610000_P01_AIR_CAD (Autodesk Fusion 360 design; units mm, degrees)
description: AIR | Thông gió | HS | P01
part number: 2026-11-01-02-30-39-384
description: AIR - AIR COLUMN | Cột gió (cụm) | HS | P01
part number: 610101
description: AIR - COLUMN FOOT PLATE | Cột gió - tấm chân | MP | P01
part number: 611106
description: AIR - COLUMN FACE - FRONT | Cột gió - mặt trước (ACP + nỉ) | MP | P01
part number: 611101
description: AIR - COLUMN FACE - LEFT | Cột gió - mặt trái (ACP + nỉ) | MP | P01
part number: 611102
description: AIR - COLUMN PLENUM SIDE PLATE - LOW | Cột gió - tấm hông buồng dưới | MP | P01
part number: 611107
description: AIR - COLUMN PLENUM SIDE PLATE - HIGH | Cột gió - tấm hông buồng trên | MP | P01
part number: 611108
description: AIR - COLUMN FILL - FRONT | Cột gió - bông - tấm trước | MP | P01
part number: 611104
description: AIR - COLUMN FILL - LEFT | Cột gió - bông - tấm trái | MP | P01
part number: 611110
description: AIR - KICK GRILLE - FRONT | Lưới gió chân cột - tấm trước | MP | P01
part number: 611105
description: AIR - KICK GRILLE - LEFT | Lưới gió chân cột - tấm trái | MP | P01
part number: 611111
description: AIR - SENSOR HUB ZONE - HOLD | Vùng bộ cảm biến (chờ) | reserved air space | P01
part number: 618101
description: AIR - COLUMN CORNER ANGLE - FRONT | Cột gió - thanh góc nhôm phía trước | MP | P01
part number: 611103
description: AIR - COLUMN CORNER ANGLE - BACK | Cột gió - thanh góc nhôm phía sau | MP | P01
part number: 611109
description: AIR - SPLITTER CARTRIDGE - COMMON | Ống tiêu âm (dùng chung cấp/thải) | HS | P01
part number: 610301
description: AIR - CARTRIDGE CASING | Vỏ ống tiêu âm nhôm 2 mm | MP | P01
part number: 611301
description: AIR - CARTRIDGE FILL - LAYER 50 | Bông tiêu âm - lớp 50 mm | MP | P01
part number: 611302
description: AIR - SOFFIT | Hộp gió trần trên cửa (cụm) | HS | P01
part number: 610201
description: AIR - SOFFIT UNDERSIDE - LEFT HINGED | Hộp gió - mặt dưới trái (bản lề, màu tối) | MP | P01
part number: 611201
description: AIR - SOFFIT UNDERSIDE - RIGHT HINGED | Hộp gió - mặt dưới phải (bản lề, màu tối) | MP | P01
part number: 611207
description: AIR - SOFFIT UNDERSIDE - FIXED OVER THE COLUMN | Hộp gió - mặt dưới cố định trên cột | MP | P01
part number: 611208
description: AIR - SOFFIT FACE - FRONT | Hộp gió - mặt trước | MP | P01
part number: 611202
description: AIR - SOFFIT TOP RAIL - DOOR SIDE | Hộp gió - thanh treo phía cửa | MP | P01
part number: 611205
description: AIR - SOFFIT TOP RAIL - ROOM SIDE | Hộp gió - thanh treo phía trong | MP | P01
part number: 611209
description: AIR - SOFFIT DOOR-SIDE PLATE | Hộp gió - tấm phía cửa | MP | P01
part number: 611210
description: AIR - SOFFIT END PLATE - LEFT | Hộp gió - tấm đầu trái | MP | P01
part number: 611206
description: AIR - SOFFIT FILL | Hộp gió - bông | MP | P01
part number: 611203
description: AIR - SOFFIT FILL - FRONT | Hộp gió - bông - tấm trước | MP | P01
part number: 611211
description: AIR - EXHAUST GRILLE | Lưới gió thải | MP | P01
part number: 611204
description: HARDWARE - SOCKET HEAD BOLT - M6 X 16 - ISO 4762 8.8 ZINC | Bulong lục giác chìm M6 × 16 | PI | P01 | the soffit's hanger stud (D-90)
part number: 838001
description: AIR - SOFFIT UNDERSIDE HINGE - HOLD | Bản lề mặt dưới hộp gió (chờ) | HOLD | P01
part number: 618105
description: AIR - SOFFIT UNDERSIDE LATCH - HOLD | Chốt bấm mặt dưới hộp gió (chờ) | HOLD | P01
part number: 618106
description: HARDWARE - SOCKET HEAD BOLT - M6 X 25 - ISO 4762 8.8 ZINC | Bulong lục giác chìm M6 × 25 (chốt mối nối khép) | PI | P01 | captive retainer HOLD (joints register)
part number: 838002
description: AIR - EXHAUST FAN BOX | Hộp quạt thải (cụm) | HS | P01
part number: 610402
description: AIR - FAN BOX CASING - EXHAUST | Vỏ hộp quạt thải nhôm 3 mm | MP | P01
part number: 611401
description: AIR - FAN BOX BULKHEAD - EXHAUST | Hộp quạt thải - vách ngăn nhôm 2 mm | MP | P01
part number: 611403
description: AIR - FAN BOX LINING - EXHAUST SIDE | Hộp quạt thải - lớp lót bên | MP | P01
part number: 611405
description: AIR - FAN BOX LINING - EXHAUST FAR END | Hộp quạt thải - lớp lót đầu xa | MP | P01
part number: 611406
description: AIR - FAN - NOCTUA NF-A14 INDUSTRIALPPC-3000 PWM | Quạt 12 V 140 mm | PI | P01
part number: 618401
description: AIR - SUPPLY FAN BOX | Hộp quạt cấp (cụm) | HS | P01
part number: 610401
description: AIR - FAN BOX CASING - SUPPLY | Vỏ hộp quạt cấp nhôm 3 mm | MP | P01
part number: 611402
description: AIR - FAN BOX BULKHEAD - SUPPLY | Hộp quạt cấp - vách ngăn | MP | P01
part number: 611404
description: AIR - FAN BOX LINING - SUPPLY END | Hộp quạt cấp - lớp lót đầu | MP | P01
part number: 611407
description: AIR - FAN BOX LIP ANGLE - SUPPLY | Hộp quạt cấp - thanh góc mép nhôm 3 mm | MP | P01
part number: 611408
description: AIR - FAN BOX PAD - SUPPLY - RUBBER 40 X 15 X 5 - HOLD | Hộp quạt cấp - đệm cao su 40 x 15 x 5 (chờ) | PI | P01
part number: 618402
description: AIR - RISER BUFFER - RUBBER - M6 - HOLD | Ống hút gió đứng - đệm cao su ren M6 (chờ) | PI | P01
part number: 618501
description: AIR - SUPPLY TRANSITION - HOLD | Ống chuyển cấp (chờ) | HOLD | P01
part number: 618102
description: AIR - INTAKE RISER | Ống hút gió đứng | MP | P01
part number: 611501
description: AIR - RISER TRANSITION - HOLD | Ống chuyển hút (chờ) | HOLD | P01
part number: 618103
description: AIR - ROOF SLEEVE | Ống thải qua mái | MP | P01
part number: 611601
description: AIR - ROOF GRILLE | Lưới thải mái | MP | P01
part number: 611602
Autodesk Fusion 360 part; units mm, degrees
(part 1 of 6)
ref_plane "WorkPlane1" through (0, 0, 0) normal (0, 0, 1) x (1, 0, 0) in component "611106 AIR - COLUMN FOOT PLATE"
sketch "OUTLINE - COLUMN FOOT PLATE" plane through (0, 0, 0) normal (0, 0, 1) x (1, 0, 0) in component "611106 AIR - COLUMN FOOT PLATE"
  line L0 (949, -641.14) -> (1161, -641.14)
  line L1 (1161, -641.14) -> (1161, -285)
  line L2 (1161, -285) -> (949, -285)
  line L3 (949, -285) -> (949, -641.14)
  dimension "d9773" = 212
  dimension "d9774" = 356.14
  dimension "d9775" = 949
  dimension "d9776" = 641.14
  constraint horizontal L0
  constraint vertical L1
  constraint horizontal L2
  constraint vertical L3
  measures "d9773" horizontal distance of L0.start L0.end
  measures "d9774" vertical distance of L0.start L2.end
  measures "d9775" horizontal distance of origin L0.start
  measures "d9776" vertical distance of origin L0.start
extrude "EXTRUDE - COLUMN FOOT PLATE" add sketch "OUTLINE - COLUMN FOOT PLATE" along normal blind 2 makes body 1 in component "611106 AIR - COLUMN FOOT PLATE"
ref_plane "WorkPlane1" through (0, 0, 112) normal (0, 0, 1) x (1, 0, 0) in component "611101 AIR - COLUMN FACE - FRONT"
sketch "OUTLINE - COLUMN FACE FRONT" plane through (0, 0, 112) normal (0, 0, 1) x (1, 0, 0) in component "611101 AIR - COLUMN FACE - FRONT"
  line L0 (949, -297) -> (1161, -297)
  line L1 (1161, -297) -> (1161, -285)
  line L2 (1161, -285) -> (949, -285)
  line L3 (949, -285) -> (949, -297)
  dimension "d9781" = 212
  dimension "d9782" = 12
  dimension "d9783" = 949
  dimension "d9784" = 297
  constraint horizontal L0
  constraint vertical L1
  constraint horizontal L2
  constraint vertical L3
  measures "d9781" horizontal distance of L0.start L0.end
  measures "d9782" vertical distance of L0.start L2.end
  measures "d9783" horizontal distance of origin L0.start
  measures "d9784" vertical distance of origin L0.start
extrude "EXTRUDE - COLUMN FACE FRONT" add sketch "OUTLINE - COLUMN FACE FRONT" along normal blind 2008 separate body makes body 2 in component "611101 AIR - COLUMN FACE - FRONT"
ref_plane "WorkPlane2" through (0, 0, 1110) normal (0, 0, 1) x (1, 0, 0) in component "611101 AIR - COLUMN FACE - FRONT"
sketch "OUTLINE - COLUMN FACE FRONT OPENING 1" plane through (0, 0, 1110) normal (0, 0, 1) x (1, 0, 0) in component "611101 AIR - COLUMN FACE - FRONT"
  line L0 (971, -337) -> (1151, -337)
  line L1 (1151, -337) -> (1151, -285)
  line L2 (1151, -285) -> (971, -285)
  line L3 (971, -285) -> (971, -337)
  dimension "d9789" = 180
  dimension "d9790" = 52
  dimension "d9791" = 971
  dimension "d9792" = 337
  constraint horizontal L0
  constraint vertical L1
  constraint horizontal L2
  constraint vertical L3
  measures "d9789" horizontal distance of L0.start L0.end
  measures "d9790" vertical distance of L0.start L2.end
  measures "d9791" horizontal distance of origin L0.start
  measures "d9792" vertical distance of origin L0.start
extrude "CUT - COLUMN FACE FRONT OPENING 1" cut sketch "OUTLINE - COLUMN FACE FRONT OPENING 1" along normal blind 180 bodies 2 in component "611101 AIR - COLUMN FACE - FRONT"
ref_plane "WorkPlane1" through (0, 0, 112) normal (0, 0, 1) x (1, 0, 0) in component "611102 AIR - COLUMN FACE - LEFT"
sketch "OUTLINE - COLUMN FACE LEFT" plane through (0, 0, 112) normal (0, 0, 1) x (1, 0, 0) in component "611102 AIR - COLUMN FACE - LEFT"
  line L0 (949, -641.14) -> (961, -641.14)
  line L1 (961, -641.14) -> (961, -297)
  line L2 (961, -297) -> (949, -297)
  line L3 (949, -297) -> (949, -641.14)
  dimension "d9797" = 12
  dimension "d9798" = 344.14
  dimension "d9799" = 949
  dimension "d9800" = 641.14
  constraint horizontal L0
  constraint vertical L1
  constraint horizontal L2
  constraint vertical L3
  measures "d9797" horizontal distance of L0.start L0.end
  measures "d9798" vertical distance of L0.start L2.end
  measures "d9799" horizontal distance of origin L0.start
  measures "d9800" vertical distance of origin L0.start
extrude "EXTRUDE - COLUMN FACE LEFT" add sketch "OUTLINE - COLUMN FACE LEFT" along normal blind 2008 separate body makes body 3 in component "611102 AIR - COLUMN FACE - LEFT"
ref_plane "WorkPlane1" through (0, 0, 2) normal (0, 0, 1) x (1, 0, 0) in component "611107 AIR - COLUMN PLENUM SIDE PLATE - LOW"
sketch "OUTLINE - COLUMN PLENUM PLATE LOW" plane through (0, 0, 2) normal (0, 0, 1) x (1, 0, 0) in component "611107 AIR - COLUMN PLENUM SIDE PLATE - LOW"
  line L0 (1160, -641.14) -> (1161, -641.14)
  line L1 (1161, -641.14) -> (1161, -317)
  line L2 (1161, -317) -> (1160, -317)
  line L3 (1160, -317) -> (1160, -641.14)
  dimension "d9805" = 1
  dimension "d9806" = 324.14
  dimension "d9807" = 1160
  dimension "d9808" = 641.14
  constraint horizontal L0
  constraint vertical L1
  constraint horizontal L2
  constraint vertical L3
  measures "d9805" horizontal distance of L0.start L0.end
  measures "d9806" vertical distance of L0.start L2.end
  measures "d9807" horizontal distance of origin L0.start
  measures "d9808" vertical distance of origin L0.start
extrude "EXTRUDE - COLUMN PLENUM PLATE LOW" add sketch "OUTLINE - COLUMN PLENUM PLATE LOW" along normal blind 138 separate body makes body 4 in component "611107 AIR - COLUMN PLENUM SIDE PLATE - LOW"
ref_plane "WorkPlane1" through (0, 0, 1890) normal (0, 0, 1) x (1, 0, 0) in component "611108 AIR - COLUMN PLENUM SIDE PLATE - HIGH"
sketch "OUTLINE - COLUMN PLENUM PLATE HIGH" plane through (0, 0, 1890) normal (0, 0, 1) x (1, 0, 0) in component "611108 AIR - COLUMN PLENUM SIDE PLATE - HIGH"
  line L0 (1160, -641.14) -> (1161, -641.14)
  line L1 (1161, -641.14) -> (1161, -317)
  line L2 (1161, -317) -> (1160, -317)
  line L3 (1160, -317) -> (1160, -641.14)
  dimension "d9813" = 1
  dimension "d9814" = 324.14
  dimension "d9815" = 1160
  dimension "d9816" = 641.14
  constraint horizontal L0
  constraint vertical L1
  constraint horizontal L2
  constraint vertical L3
  measures "d9813" horizontal distance of L0.start L0.end
  measures "d9814" vertical distance of L0.start L2.end
  measures "d9815" horizontal distance of origin L0.start
  measures "d9816" vertical distance of origin L0.start
extrude "EXTRUDE - COLUMN PLENUM PLATE HIGH" add sketch "OUTLINE - COLUMN PLENUM PLATE HIGH" along normal blind 230 separate body makes body 5 in component "611108 AIR - COLUMN PLENUM SIDE PLATE - HIGH"
ref_plane "WorkPlane1" through (0, 0, 140) normal (0, 0, 1) x (1, 0, 0) in component "611104 AIR - COLUMN FILL - FRONT"
sketch "OUTLINE - COLUMN FILL FRONT" plane through (0, 0, 140) normal (0, 0, 1) x (1, 0, 0) in component "611104 AIR - COLUMN FILL - FRONT"
  line L0 (970, -322.14) -> (1152, -322.14)
  line L1 (1152, -322.14) -> (1152, -297)
  line L2 (1152, -297) -> (970, -297)
  line L3 (970, -297) -> (970, -322.14)
  dimension "d9821" = 182
  dimension "d9822" = 25.14
  dimension "d9823" = 970
  dimension "d9824" = 322.14
  constraint horizontal L0
  constraint vertical L1
  constraint horizontal L2
  constraint vertical L3
  measures "d9821" horizontal distance of L0.start L0.end
  measures "d9822" vertical distance of L0.start L2.end
  measures "d9823" horizontal distance of origin L0.start
  measures "d9824" vertical distance of origin L0.start
extrude "EXTRUDE - COLUMN FILL FRONT" add sketch "OUTLINE - COLUMN FILL FRONT" along normal blind 1750 separate body makes body 6 in component "611104 AIR - COLUMN FILL - FRONT"
ref_plane "WorkPlane2" through (0, 0, 1110) normal (0, 0, 1) x (1, 0, 0) in component "611104 AIR - COLUMN FILL - FRONT"
sketch "OUTLINE - COLUMN FILL FRONT OPENING 1" plane through (0, 0, 1110) normal (0, 0, 1) x (1, 0, 0) in component "611104 AIR - COLUMN FILL - FRONT"
  line L0 (971, -337) -> (1151, -337)
  line L1 (1151, -337) -> (1151, -285)
  line L2 (1151, -285) -> (971, -285)
  line L3 (971, -285) -> (971, -337)
  dimension "d9829" = 180
  dimension "d9830" = 52
  dimension "d9831" = 971
  dimension "d9832" = 337
  constraint horizontal L0
  constraint vertical L1
  constraint horizontal L2
  constraint vertical L3
  measures "d9829" horizontal distance of L0.start L0.end
  measures "d9830" vertical distance of L0.start L2.end
  measures "d9831" horizontal distance of origin L0.start
  measures "d9832" vertical distance of origin L0.start
extrude "CUT - COLUMN FILL FRONT OPENING 1" cut sketch "OUTLINE - COLUMN FILL FRONT OPENING 1" along normal blind 180 bodies 6 in component "611104 AIR - COLUMN FILL - FRONT"
ref_plane "WorkPlane1" through (0, 0, 140) normal (0, 0, 1) x (1, 0, 0) in component "611110 AIR - COLUMN FILL - LEFT"
sketch "OUTLINE - COLUMN FILL LEFT" plane through (0, 0, 140) normal (0, 0, 1) x (1, 0, 0) in component "611110 AIR - COLUMN FILL - LEFT"
  line L0 (961, -621.14) -> (988, -621.14)
  line L1 (988, -621.14) -> (988, -322.14)
  line L2 (988, -322.14) -> (961, -322.14)
  line L3 (961, -322.14) -> (961, -621.14)
  dimension "d9837" = 27
  dimension "d9839" = 961
  dimension "d9840" = 621.14
  constraint horizontal L0
  constraint vertical L1
  constraint horizontal L2
  constraint vertical L3
  measures "d9837" horizontal distance of L0.start L0.end
  measures "d9839" horizontal distance of origin L0.start
  measures "d9840" vertical distance of origin L0.start
extrude "EXTRUDE - COLUMN FILL LEFT" add sketch "OUTLINE - COLUMN FILL LEFT" along normal blind 1750 separate body makes body 7 in component "611110 AIR - COLUMN FILL - LEFT"
ref_plane "WorkPlane1" through (0, 0, 12) normal (0, 0, 1) x (1, 0, 0) in component "611105 AIR - KICK GRILLE - FRONT"
sketch "OUTLINE - KICK GRILLE FRONT" plane through (0, 0, 12) normal (0, 0, 1) x (1, 0, 0) in component "611105 AIR - KICK GRILLE - FRONT"
  line L0 (949, -287) -> (1161, -287)
  line L1 (1161, -287) -> (1161, -285)
  line L2 (1161, -285) -> (949, -285)
  line L3 (949, -285) -> (949, -287)
  dimension "d9845" = 212
  dimension "d9846" = 2
  dimension "d9847" = 949
  dimension "d9848" = 287
  constraint horizontal L0
  constraint vertical L1
  constraint horizontal L2
  constraint vertical L3
  measures "d9845" horizontal distance of L0.start L0.end
  measures "d9846" vertical distance of L0.start L2.end
  measures "d9847" horizontal distance of origin L0.start
  measures "d9848" vertical distance of origin L0.start
extrude "EXTRUDE - KICK GRILLE FRONT" add sketch "OUTLINE - KICK GRILLE FRONT" along normal blind 100 separate body makes body 8 in component "611105 AIR - KICK GRILLE - FRONT"
ref_plane "WorkPlane1" through (0, 0, 12) normal (0, 0, 1) x (1, 0, 0) in component "611111 AIR - KICK GRILLE - LEFT"
sketch "OUTLINE - KICK GRILLE LEFT" plane through (0, 0, 12) normal (0, 0, 1) x (1, 0, 0) in component "611111 AIR - KICK GRILLE - LEFT"
  line L0 (949, -599) -> (951, -599)
  line L1 (951, -599) -> (951, -287)
  line L2 (951, -287) -> (949, -287)
  line L3 (949, -287) -> (949, -599)
  dimension "d9853" = 2
  dimension "d9854" = 312
  dimension "d9855" = 949
  dimension "d9856" = 599
  constraint horizontal L0
  constraint vertical L1
  constraint horizontal L2
  constraint vertical L3
  measures "d9853" horizontal distance of L0.start L0.end
  measures "d9854" vertical distance of L0.start L2.end
  measures "d9855" horizontal distance of origin L0.start
  measures "d9856" vertical distance of origin L0.start
extrude "EXTRUDE - KICK GRILLE LEFT" add sketch "OUTLINE - KICK GRILLE LEFT" along normal blind 100 separate body makes body 9 in component "611111 AIR - KICK GRILLE - LEFT"
ref_plane "WorkPlane1" through (0, 0, 1110) normal (0, 0, 1) x (1, 0, 0) in component "618101 AIR - SENSOR HUB ZONE - HOLD"
sketch "OUTLINE - SENSOR HUB ZONE" plane through (0, 0, 1110) normal (0, 0, 1) x (1, 0, 0) in component "618101 AIR - SENSOR HUB ZONE - HOLD"
  line L0 (971, -314) -> (1151, -314)
  line L1 (1151, -314) -> (1151, -285)
  line L2 (1151, -285) -> (971, -285)
  line L3 (971, -285) -> (971, -314)
  dimension "d9861" = 180
  dimension "d9862" = 29
  dimension "d9863" = 971
  dimension "d9864" = 314
  constraint horizontal L0
  constraint vertical L1
  constraint horizontal L2
  constraint vertical L3
  measures "d9861" horizontal distance of L0.start L0.end
  measures "d9862" vertical distance of L0.start L2.end
  measures "d9863" horizontal distance of origin L0.start
  measures "d9864" vertical distance of origin L0.start
extrude "EXTRUDE - SENSOR HUB ZONE" add sketch "OUTLINE - SENSOR HUB ZONE" along normal blind 180 separate body makes body 10 in component "618101 AIR - SENSOR HUB ZONE - HOLD"
sketch "PROFILE - COLUMN ANGLE FRONT" plane through (0, 0, 0) normal (0, 0, 1) x (1, 0, 0) in component "611103 AIR - COLUMN CORNER ANGLE - FRONT"
  line L0 (0, 20) -> (9, 20)
  line L1 (9, 20) -> (9, 18)
  line L2 (9, 18) -> (2, 18)
  line L3 (2, 18) -> (2, 0)
  line L4 (2, 0) -> (0, 0)
  line L5 (0, 0) -> (0, 20)
  dimension "d9867" = 0
  dimension "d9868" = 20
  dimension "d9869" = 9
  dimension "d9870" = 18
  dimension "d9871" = 2
  dimension "d9872" = 0
  constraint horizontal L0
  constraint vertical L1
  constraint horizontal L2
  constraint vertical L3
  constraint horizontal L4
  constraint vertical L5
  measures "d9867" horizontal distance of L4.end L0.start
  measures "d9868" vertical distance of L4.end L0.start
  measures "d9869" horizontal distance of L4.end L0.end
  measures "d9870" vertical distance of L4.end L1.end
  measures "d9871" horizontal distance of L4.end L2.end
  measures "d9872" vertical distance of L4.end L3.end
extrude "EXTRUDE - COLUMN ANGLE FRONT" add sketch "PROFILE - COLUMN ANGLE FRONT" along normal blind 2118 separate body makes body 11 in component "611103 AIR - COLUMN CORNER ANGLE - FRONT"
ref_plane "WorkPlane1" through (0, 0, 2) normal (0, 0, 1) x (1, 0, 0) in component "610101 AIR - AIR COLUMN"
sketch "PLACE - COLUMN ANGLE FL" plane through (0, 0, 2) normal (0, 0, 1) x (1, 0, 0) in component "610101 AIR - AIR COLUMN"
  point P0 (961, -317)
  dimension "d9877" = 961
  dimension "d9878" = 317
  measures "d9877" horizontal distance of origin P0
  measures "d9878" vertical distance of origin P0
ref_plane "WorkPlane2" through (0, 0, 2120) normal (0, 0, 1) x (1, 0, 0) in component "610101 AIR - AIR COLUMN"
sketch "PLACE - COLUMN ANGLE FR" plane through (0, 0, 2120) normal (0, 0, 1) x (1, 0, 0) in component "610101 AIR - AIR COLUMN"
  point P0 (1161, -317)
  dimension "d9885" = 1161
  dimension "d9886" = 317
  measures "d9885" horizontal distance of origin P0
  measures "d9886" vertical distance of origin P0
ref_plane "WorkPlane1" through (0, 0, 2) normal (0, 0, 1) x (1, 0, 0) in component "611109 AIR - COLUMN CORNER ANGLE - BACK"
sketch "PROFILE - COLUMN ANGLE BL" plane through (0, 0, 2) normal (0, 0, 1) x (1, 0, 0) in component "611109 AIR - COLUMN CORNER ANGLE - BACK"
  line L0 (961, -641.14) -> (981, -641.14)
  line L1 (981, -641.14) -> (981, -639.14)
  line L2 (981, -639.14) -> (963, -639.14)
  line L3 (963, -639.14) -> (963, -621.14)
  line L4 (963, -621.14) -> (961, -621.14)
  line L5 (961, -621.14) -> (961, -641.14)
  dimension "d9893" = 961
  dimension "d9894" = 641.14
  dimension "d9895" = 981
  dimension "d9896" = 639.14
  dimension "d9897" = 963
  dimension "d9898" = 621.14
  constraint horizontal L0
  constraint vertical L1
  constraint horizontal L2
  constraint vertical L3
  constraint horizontal L4
  constraint vertical L5
  measures "d9893" horizontal distance of origin L0.start
  measures "d9894" vertical distance of origin L0.start
  measures "d9895" horizontal distance of origin L0.end
  measures "d9896" vertical distance of origin L1.end
  measures "d9897" horizontal distance of origin L2.end
  measures "d9898" vertical distance of origin L3.end
extrude "EXTRUDE - COLUMN ANGLE BL" add sketch "PROFILE - COLUMN ANGLE BL" along normal blind 2118 separate body makes body 12 in component "611109 AIR - COLUMN CORNER ANGLE - BACK"
ref_plane "WorkPlane1" through (0, 0, 140) normal (0, 0, 1) x (1, 0, 0) in component "611301 AIR - CARTRIDGE CASING"
sketch "OUTLINE - CARTRIDGE SUPPLY" plane through (0, 0, 140) normal (0, 0, 1) x (1, 0, 0) in component "611301 AIR - CARTRIDGE CASING"
  line L0 (988, -636.14) -> (1161, -636.14)
  line L1 (1161, -636.14) -> (1161, -322.14)
  line L2 (1161, -322.14) -> (988, -322.14)
  line L3 (988, -322.14) -> (988, -636.14)
  dimension "d9903" = 173
  dimension "d9905" = 988
  dimension "d9906" = 636.14
  constraint horizontal L0
  constraint vertical L1
  constraint horizontal L2
  constraint vertical L3
  measures "d9903" horizontal distance of L0.start L0.end
  measures "d9905" horizontal distance of origin L0.start
  measures "d9906" vertical distance of origin L0.start
extrude "EXTRUDE - CARTRIDGE SUPPLY" add sketch "OUTLINE - CARTRIDGE SUPPLY" along normal blind 1750 separate body makes body 13 in component "611301 AIR - CARTRIDGE CASING"
shell "SHELL - CARTRIDGE SUPPLY CASING" thickness 2 removed faces 2 at (1045.6667, -426.8067, 1890) at (1045.6667, -426.8067, 140) on bodies 13 in component "611301 AIR - CARTRIDGE CASING"
sketch "OUTLINE - LAYER 50 SUPPLY" plane through (0, 0, 0) normal (0, 0, 1) x (1, 0, 0) in component "611302 AIR - CARTRIDGE FILL - LAYER 50"
  line L0 (0, 0) -> (169, 0)
  line L1 (169, 0) -> (169, 50)
  line L2 (169, 50) -> (0, 50)
  line L3 (0, 50) -> (0, 0)
  dimension "d9910" = 169
  dimension "d9911" = 50
  constraint horizontal L0
  constraint vertical L1
  constraint horizontal L2
  constraint vertical L3
  constraint vertical L0.start L3.end
  constraint horizontal L0.start L3.end
  measures "d9910" horizontal distance of L0.start L0.end
  measures "d9911" vertical distance of L0.start L2.end
extrude "EXTRUDE - LAYER 50 SUPPLY" add sketch "OUTLINE - LAYER 50 SUPPLY" along normal blind 1750 separate body makes body 14 in component "611302 AIR - CARTRIDGE FILL - LAYER 50"
ref_plane "WorkPlane1" through (0, 0, 140) normal (0, 0, 1) x (1, 0, 0) in component "610301 AIR - SPLITTER CARTRIDGE - COMMON (SUPPLY)"
sketch "PLACE - LAYER 1 SUPPLY" plane through (0, 0, 140) normal (0, 0, 1) x (1, 0, 0) in component "610301 AIR - SPLITTER CARTRIDGE - COMMON (SUPPLY)"
  point P0 (990, -634.14)
  dimension "d9916" = 990
  dimension "d9917" = 634.14
  measures "d9916" horizontal distance of origin P0
  measures "d9917" vertical distance of origin P0
ref_plane "WorkPlane2" through (0, 0, 140) normal (0, 0, 1) x (1, 0, 0) in component "610301 AIR - SPLITTER CARTRIDGE - COMMON (SUPPLY)"
sketch "PLACE - LAYER 2 SUPPLY" plane through (0, 0, 140) normal (0, 0, 1) x (1, 0, 0) in component "610301 AIR - SPLITTER CARTRIDGE - COMMON (SUPPLY)"
  point P0 (990, -504.14)
  dimension "d9924" = 990
  dimension "d9925" = 504.14
  measures "d9924" horizontal distance of origin P0
  measures "d9925" vertical distance of origin P0
ref_plane "WorkPlane3" through (0, 0, 140) normal (0, 0, 1) x (1, 0, 0) in component "610301 AIR - SPLITTER CARTRIDGE - COMMON (SUPPLY)"
sketch "PLACE - LAYER 3 SUPPLY" plane through (0, 0, 140) normal (0, 0, 1) x (1, 0, 0) in component "610301 AIR - SPLITTER CARTRIDGE - COMMON (SUPPLY)"
  point P0 (990, -374.14)
  dimension "d9932" = 990
  dimension "d9933" = 374.14
  measures "d9932" horizontal distance of origin P0
  measures "d9933" vertical distance of origin P0
ref_plane "WorkPlane1" through (0, 0, 2120) normal (0, 0, 1) x (1, 0, 0) in component "611201 AIR - SOFFIT UNDERSIDE - LEFT HINGED"
sketch "OUTLINE - SOFFIT UNDERSIDE LEFT" plane through (0, 0, 2120) normal (0, 0, 1) x (1, 0, 0) in component "611201 AIR - SOFFIT UNDERSIDE - LEFT HINGED"
  line L0 (-1161, -641.14) -> (-1, -641.14)
  line L1 (-1, -641.14) -> (-1, -297)
  line L2 (-1, -297) -> (-1161, -297)
  line L3 (-1161, -297) -> (-1161, -641.14)
  dimension "d9940" = 1160
  dimension "d9941" = 344.14
  dimension "d9942" = 1161
  dimension "d9943" = 641.14
  constraint horizontal L0
  constraint vertical L1
  constraint horizontal L2
  constraint vertical L3
  measures "d9940" horizontal distance of L0.start L0.end
  measures "d9941" vertical distance of L0.start L2.end
  measures "d9942" horizontal distance of origin L0.start
  measures "d9943" vertical distance of origin L0.start
extrude "EXTRUDE - SOFFIT UNDERSIDE LEFT" add sketch "OUTLINE - SOFFIT UNDERSIDE LEFT" along normal blind 12 separate body makes body 15 in component "611201 AIR - SOFFIT UNDERSIDE - LEFT HINGED"
ref_plane "WorkPlane2" through (0, 0, 2120) normal (0, 0, 1) x (1, 0, 0) in component "611201 AIR - SOFFIT UNDERSIDE - LEFT HINGED"
sketch "OUTLINE - SOFFIT UNDERSIDE LEFT OPENING 1" plane through (0, 0, 2120) normal (0, 0, 1) x (1, 0, 0) in component "611201 AIR - SOFFIT UNDERSIDE - LEFT HINGED"
  line L0 (-1150, -633) -> (-885, -633)
  line L1 (-885, -633) -> (-885, -297)
  line L2 (-885, -297) -> (-1150, -297)
  line L3 (-1150, -297) -> (-1150, -633)
  dimension "d9948" = 265
  dimension "d9949" = 336
  dimension "d9950" = 1150
  dimension "d9951" = 633
  constraint horizontal L0
  constraint vertical L1
  constraint horizontal L2
  constraint vertical L3
  measures "d9948" horizontal distance of L0.start L0.end
  measures "d9949" vertical distance of L0.start L2.end
  measures "d9950" horizontal distance of origin L0.start
  measures "d9951" vertical distance of origin L0.start
extrude "CUT - SOFFIT UNDERSIDE LEFT OPENING 1" cut sketch "OUTLINE - SOFFIT UNDERSIDE LEFT OPENING 1" along normal blind 12 bodies 15 in component "611201 AIR - SOFFIT UNDERSIDE - LEFT HINGED"
ref_plane "WorkPlane1" through (0, 0, 2120) normal (0, 0, 1) x (1, 0, 0) in component "611207 AIR - SOFFIT UNDERSIDE - RIGHT HINGED"
sketch "OUTLINE - SOFFIT UNDERSIDE RIGHT" plane through (0, 0, 2120) normal (0, 0, 1) x (1, 0, 0) in component "611207 AIR - SOFFIT UNDERSIDE - RIGHT HINGED"
  line L0 (1, -641.14) -> (948, -641.14)
  line L1 (948, -641.14) -> (948, -297)
  line L2 (948, -297) -> (1, -297)
  line L3 (1, -297) -> (1, -641.14)
  dimension "d9956" = 947
  dimension "d9957" = 344.14
  dimension "d9958" = 1
  dimension "d9959" = 641.14
  constraint horizontal L0
  constraint vertical L1
  constraint horizontal L2
  constraint vertical L3
  measures "d9956" horizontal distance of L0.start L0.end
  measures "d9957" vertical distance of L0.start L2.end
  measures "d9958" horizontal distance of origin L0.start
  measures "d9959" vertical distance of origin L0.start
extrude "EXTRUDE - SOFFIT UNDERSIDE RIGHT" add sketch "OUTLINE - SOFFIT UNDERSIDE RIGHT" along normal blind 12 separate body makes body 16 in component "611207 AIR - SOFFIT UNDERSIDE - RIGHT HINGED"
ref_plane "WorkPlane1" through (0, 0, 2120) normal (0, 0, 1) x (1, 0, 0) in component "611208 AIR - SOFFIT UNDERSIDE - FIXED OVER THE COLUMN"
sketch "OUTLINE - SOFFIT UNDERSIDE FIXED" plane through (0, 0, 2120) normal (0, 0, 1) x (1, 0, 0) in component "611208 AIR - SOFFIT UNDERSIDE - FIXED OVER THE COLUMN"
  line L0 (949, -641.14) -> (1161, -641.14)
  line L1 (1161, -641.14) -> (1161, -297)
  line L2 (1161, -297) -> (949, -297)
  line L3 (949, -297) -> (949, -641.14)
  dimension "d9964" = 212
  dimension "d9965" = 344.14
  dimension "d9966" = 949
  dimension "d9967" = 641.14
  constraint horizontal L0
  constraint vertical L1
  constraint horizontal L2
  constraint vertical L3
  measures "d9964" horizontal distance of L0.start L0.end
  measures "d9965" vertical distance of L0.start L2.end
  measures "d9966" horizontal distance of origin L0.start
  measures "d9967" vertical distance of origin L0.start
extrude "EXTRUDE - SOFFIT UNDERSIDE FIXED" add sketch "OUTLINE - SOFFIT UNDERSIDE FIXED" along normal blind 12 separate body makes body 17 in component "611208 AIR - SOFFIT UNDERSIDE - FIXED OVER THE COLUMN"
ref_plane "WorkPlane1" through (0, 0, 2120) normal (0, 0, 1) x (1, 0, 0) in component "611202 AIR - SOFFIT FACE - FRONT"
sketch "OUTLINE - SOFFIT FACE FRONT" plane through (0, 0, 2120) normal (0, 0, 1) x (1, 0, 0) in component "611202 AIR - SOFFIT FACE - FRONT"
  line L0 (-1161, -297) -> (1161, -297)
  line L1 (1161, -297) -> (1161, -285)
  line L2 (1161, -285) -> (-1161, -285)
  line L3 (-1161, -285) -> (-1161, -297)
  dimension "d9972" = 2322
  dimension "d9973" = 12
  dimension "d9974" = 1161
  dimension "d9975" = 297
  constraint horizontal L0
  constraint vertical L1
  constraint horizontal L2
  constraint vertical L3
  measures "d9972" horizontal distance of L0.start L0.end
  measures "d9973" vertical distance of L0.start L2.end
  measures "d9974" horizontal distance of origin L0.start
  measures "d9975" vertical distance of origin L0.start
extrude "EXTRUDE - SOFFIT FACE FRONT" add sketch "OUTLINE - SOFFIT FACE FRONT" along normal blind 226.24 separate body makes body 18 in component "611202 AIR - SOFFIT FACE - FRONT"
ref_plane "WorkPlane2" through (0, 0, 2338.74) normal (0, 0, 1) x (1, 0, 0) in component "611202 AIR - SOFFIT FACE - FRONT"
sketch "OUTLINE - SOFFIT FACE FRONT OPENING 1" plane through (0, 0, 2338.74) normal (0, 0, 1) x (1, 0, 0) in component "611202 AIR - SOFFIT FACE - FRONT"
  line L0 (-589.5, -297) -> (-576.5, -297)
  line L1 (-576.5, -297) -> (-576.5, -285)
  line L2 (-576.5, -285) -> (-589.5, -285)
  line L3 (-589.5, -285) -> (-589.5, -297)
  dimension "d9980" = 13
  dimension "d9981" = 12
  dimension "d9982" = 589.5
  dimension "d9983" = 297
  constraint horizontal L0
  constraint vertical L1
  constraint horizontal L2
  constraint vertical L3
  measures "d9980" horizontal distance of L0.start L0.end
  measures "d9981" vertical distance of L0.start L2.end
  measures "d9982" horizontal distance of origin L0.start
  measures "d9983" vertical distance of origin L0.start
extrude "CUT - SOFFIT FACE FRONT OPENING 1" cut sketch "OUTLINE - SOFFIT FACE FRONT OPENING 1" along normal blind 7.5 bodies 18 in component "611202 AIR - SOFFIT FACE - FRONT"
ref_plane "WorkPlane3" through (0, 0, 2338.74) normal (0, 0, 1) x (1, 0, 0) in component "611202 AIR - SOFFIT FACE - FRONT"
sketch "OUTLINE - SOFFIT FACE FRONT OPENING 2" plane through (0, 0, 2338.74) normal (0, 0, 1) x (1, 0, 0) in component "611202 AIR - SOFFIT FACE - FRONT"
  line L0 (576.5, -297) -> (589.5, -297)
  line L1 (589.5, -297) -> (589.5, -285)
  line L2 (589.5, -285) -> (576.5, -285)
  line L3 (576.5, -285) -> (576.5, -297)
  dimension "d9988" = 13
  dimension "d9989" = 12
  dimension "d9990" = 576.5
  dimension "d9991" = 297
  constraint horizontal L0
  constraint vertical L1
  constraint horizontal L2
  constraint vertical L3
  measures "d9988" horizontal distance of L0.start L0.end
  measures "d9989" vertical distance of L0.start L2.end
  measures "d9990" horizontal distance of origin L0.start
  measures "d9991" vertical distance of origin L0.start
extrude "CUT - SOFFIT FACE FRONT OPENING 2" cut sketch "OUTLINE - SOFFIT FACE FRONT OPENING 2" along normal blind 7.5 bodies 18 in component "611202 AIR - SOFFIT FACE - FRONT"
ref_plane "WorkPlane4" through (0, 0, 2338.74) normal (0, 0, 1) x (1, 0, 0) in component "611202 AIR - SOFFIT FACE - FRONT"
sketch "OUTLINE - SOFFIT FACE FRONT OPENING 3" plane through (0, 0, 2338.74) normal (0, 0, 1) x (1, 0, 0) in component "611202 AIR - SOFFIT FACE - FRONT"
  line L0 (-1106.5, -297) -> (-1093.5, -297)
  line L1 (-1093.5, -297) -> (-1093.5, -285)
  line L2 (-1093.5, -285) -> (-1106.5, -285)
  line L3 (-1106.5, -285) -> (-1106.5, -297)
  dimension "d9996" = 13
  dimension "d9997" = 12
  dimension "d9998" = 1106.5
  dimension "d9999" = 297
  constraint horizontal L0
  constraint vertical L1
  constraint horizontal L2
  constraint vertical L3
  measures "d9996" horizontal distance of L0.start L0.end
  measures "d9997" vertical distance of L0.start L2.end
  measures "d9998" horizontal distance of origin L0.start
  measures "d9999" vertical distance of origin L0.start
extrude "CUT - SOFFIT FACE FRONT OPENING 3" cut sketch "OUTLINE - SOFFIT FACE FRONT OPENING 3" along normal blind 7.5 bodies 18 in component "611202 AIR - SOFFIT FACE - FRONT"
ref_plane "WorkPlane5" through (0, 0, 2338.74) normal (0, 0, 1) x (1, 0, 0) in component "611202 AIR - SOFFIT FACE - FRONT"
sketch "OUTLINE - SOFFIT FACE FRONT OPENING 4" plane through (0, 0, 2338.74) normal (0, 0, 1) x (1, 0, 0) in component "611202 AIR - SOFFIT FACE - FRONT"
  line L0 (-956.5, -297) -> (-943.5, -297)
  line L1 (-943.5, -297) -> (-943.5, -285)
  line L2 (-943.5, -285) -> (-956.5, -285)
  line L3 (-956.5, -285) -> (-956.5, -297)
  dimension "d10004" = 13
  dimension "d10005" = 12
  dimension "d10006" = 956.5
  dimension "d10007" = 297
  constraint horizontal L0
  constraint vertical L1
  constraint horizontal L2
  constraint vertical L3
  measures "d10004" horizontal distance of L0.start L0.end
  measures "d10005" vertical distance of L0.start L2.end
  measures "d10006" horizontal distance of origin L0.start
  measures "d10007" vertical distance of origin L0.start
extrude "CUT - SOFFIT FACE FRONT OPENING 4" cut sketch "OUTLINE - SOFFIT FACE FRONT OPENING 4" along normal blind 7.5 bodies 18 in component "611202 AIR - SOFFIT FACE - FRONT"
ref_plane "WorkPlane1" through (0, 0, 2346.24) normal (0, 0, 1) x (1, 0, 0) in component "611205 AIR - SOFFIT TOP RAIL - DOOR SIDE"
sketch "OUTLINE - SOFFIT RAIL DOOR" plane through (0, 0, 2346.24) normal (0, 0, 1) x (1, 0, 0) in component "611205 AIR - SOFFIT TOP RAIL - DOOR SIDE"
  line L0 (-1161, -641.14) -> (1161, -641.14)
  line L1 (1161, -641.14) -> (1161, -621)
  line L2 (1161, -621) -> (-1161, -621)
  line L3 (-1161, -621) -> (-1161, -641.14)
  dimension "d10012" = 2322
  dimension "d10013" = 20.14
  dimension "d10014" = 1161
  dimension "d10015" = 641.14
  constraint horizontal L0
  constraint vertical L1
  constraint horizontal L2
  constraint vertical L3
  measures "d10012" horizontal distance of L0.start L0.end
  measures "d10013" vertical distance of L0.start L2.end
  measures "d10014" horizontal distance of origin L0.start
  measures "d10015" vertical distance of origin L0.start
extrude "EXTRUDE - SOFFIT RAIL DOOR" add sketch "OUTLINE - SOFFIT RAIL DOOR" along normal blind 3 separate body makes body 19 in component "611205 AIR - SOFFIT TOP RAIL - DOOR SIDE"
ref_plane "WorkPlane1" through (0, 0, 2346.24) normal (0, 0, 1) x (1, 0, 0) in component "611209 AIR - SOFFIT TOP RAIL - ROOM SIDE"
sketch "OUTLINE - SOFFIT RAIL ROOM" plane through (0, 0, 2346.24) normal (0, 0, 1) x (1, 0, 0) in component "611209 AIR - SOFFIT TOP RAIL - ROOM SIDE"
  line L0 (-1161, -309) -> (1161, -309)
  line L1 (1161, -309) -> (1161, -285)
  line L2 (1161, -285) -> (-1161, -285)
  line L3 (-1161, -285) -> (-1161, -309)
  dimension "d10020" = 2322
  dimension "d10021" = 24
  dimension "d10022" = 1161
  dimension "d10023" = 309
  constraint horizontal L0
  constraint vertical L1
  constraint horizontal L2
  constraint vertical L3
  measures "d10020" horizontal distance of L0.start L0.end
  measures "d10021" vertical distance of L0.start L2.end
  measures "d10022" horizontal distance of origin L0.start
  measures "d10023" vertical distance of origin L0.start
extrude "EXTRUDE - SOFFIT RAIL ROOM" add sketch "OUTLINE - SOFFIT RAIL ROOM" along normal blind 3 separate body makes body 20 in component "611209 AIR - SOFFIT TOP RAIL - ROOM SIDE"
ref_plane "WorkPlane1" through (0, 0, 2140) normal (0, 0, 1) x (1, 0, 0) in component "611210 AIR - SOFFIT DOOR-SIDE PLATE"
sketch "OUTLINE - SOFFIT DOOR PLATE" plane through (0, 0, 2140) normal (0, 0, 1) x (1, 0, 0) in component "611210 AIR - SOFFIT DOOR-SIDE PLATE"
  line L0 (-1161, -641.14) -> (1161, -641.14)
  line L1 (1161, -641.14) -> (1161, -639.14)
  line L2 (1161, -639.14) -> (-1161, -639.14)
  line L3 (-1161, -639.14) -> (-1161, -641.14)
  dimension "d10028" = 2322
  dimension "d10030" = 1161
  dimension "d10031" = 641.14
  constraint horizontal L0
  constraint vertical L1
  constraint horizontal L2
  constraint vertical L3
  measures "d10028" horizontal distance of L0.start L0.end
  measures "d10030" horizontal distance of origin L0.start
  measures "d10031" vertical distance of origin L0.start
extrude "EXTRUDE - SOFFIT DOOR PLATE" add sketch "OUTLINE - SOFFIT DOOR PLATE" along normal blind 206.24 separate body makes body 21 in component "611210 AIR - SOFFIT DOOR-SIDE PLATE"
ref_plane "WorkPlane2" through (0, 0, 2338.74) normal (0, 0, 1) x (1, 0, 0) in component "611210 AIR - SOFFIT DOOR-SIDE PLATE"
sketch "OUTLINE - SOFFIT DOOR PLATE OPENING 1" plane through (0, 0, 2338.74) normal (0, 0, 1) x (1, 0, 0) in component "611210 AIR - SOFFIT DOOR-SIDE PLATE"
  line L0 (-589.5, -641.14) -> (-576.5, -641.14)
  line L1 (-576.5, -641.14) -> (-576.5, -639.14)
  line L2 (-576.5, -639.14) -> (-589.5, -639.14)
  line L3 (-589.5, -639.14) -> (-589.5, -641.14)
  dimension "d10036" = 13
  dimension "d10038" = 589.5
  dimension "d10039" = 641.14
  constraint horizontal L0
  constraint vertical L1
  constraint horizontal L2
  constraint vertical L3
  measures "d10036" horizontal distance of L0.start L0.end
  measures "d10038" horizontal distance of origin L0.start
  measures "d10039" vertical distance of origin L0.start
extrude "CUT - SOFFIT DOOR PLATE OPENING 1" cut sketch "OUTLINE - SOFFIT DOOR PLATE OPENING 1" along normal blind 7.5 bodies 21 in component "611210 AIR - SOFFIT DOOR-SIDE PLATE"
ref_plane "WorkPlane3" through (0, 0, 2338.74) normal (0, 0, 1) x (1, 0, 0) in component "611210 AIR - SOFFIT DOOR-SIDE PLATE"
sketch "OUTLINE - SOFFIT DOOR PLATE OPENING 2" plane through (0, 0, 2338.74) normal (0, 0, 1) x (1, 0, 0) in component "611210 AIR - SOFFIT DOOR-SIDE PLATE"
  line L0 (576.5, -641.14) -> (589.5, -641.14)
  line L1 (589.5, -641.14) -> (589.5, -639.14)
  line L2 (589.5, -639.14) -> (576.5, -639.14)
  line L3 (576.5, -639.14) -> (576.5, -641.14)
  dimension "d10044" = 13
  dimension "d10046" = 576.5
  dimension "d10047" = 641.14
  constraint horizontal L0
  constraint vertical L1
  constraint horizontal L2
  constraint vertical L3
  measures "d10044" horizontal distance of L0.start L0.end
  measures "d10046" horizontal distance of origin L0.start
  measures "d10047" vertical distance of origin L0.start
extrude "CUT - SOFFIT DOOR PLATE OPENING 2" cut sketch "OUTLINE - SOFFIT DOOR PLATE OPENING 2" along normal blind 7.5 bodies 21 in component "611210 AIR - SOFFIT DOOR-SIDE PLATE"
ref_plane "WorkPlane1" through (0, 0, 2132) normal (0, 0, 1) x (1, 0, 0) in component "611206 AIR - SOFFIT END PLATE - LEFT"
sketch "OUTLINE - SOFFIT END PLATE LEFT" plane through (0, 0, 2132) normal (0, 0, 1) x (1, 0, 0) in component "611206 AIR - SOFFIT END PLATE - LEFT"
  line L0 (-1161, -639.14) -> (-1159, -639.14)
  line L1 (-1159, -639.14) -> (-1159, -297)
  line L2 (-1159, -297) -> (-1161, -297)
  line L3 (-1161, -297) -> (-1161, -639.14)
  dimension "d10052" = 2
  dimension "d10053" = 342.14
  dimension "d10054" = 1161
  dimension "d10055" = 639.14
  constraint horizontal L0
  constraint vertical L1
  constraint horizontal L2
  constraint vertical L3
  measures "d10052" horizontal distance of L0.start L0.end
  measures "d10053" vertical distance of L0.start L2.end
  measures "d10054" horizontal distance of origin L0.start
  measures "d10055" vertical distance of origin L0.start
extrude "EXTRUDE - SOFFIT END PLATE LEFT" add sketch "OUTLINE - SOFFIT END PLATE LEFT" along normal blind 206.74 separate body makes body 22 in component "611206 AIR - SOFFIT END PLATE - LEFT"
ref_plane "WorkPlane1" through (0, 0, 2132) normal (0, 0, 1) x (1, 0, 0) in component "611203 AIR - SOFFIT FILL"
sketch "OUTLINE - SOFFIT FILL UNDER" plane through (0, 0, 2132) normal (0, 0, 1) x (1, 0, 0) in component "611203 AIR - SOFFIT FILL"
  line L0 (-883, -636.14) -> (1161, -636.14)
  line L1 (1161, -636.14) -> (1161, -305)
  line L2 (1161, -305) -> (-883, -305)
  line L3 (-883, -305) -> (-883, -636.14)
  dimension "d10060" = 2044
  dimension "d10061" = 331.14
  dimension "d10062" = 883
  dimension "d10063" = 636.14
  constraint horizontal L0
  constraint vertical L1
  constraint horizontal L2
  constraint vertical L3
  measures "d10060" horizontal distance of L0.start L0.end
  measures "d10061" vertical distance of L0.start L2.end
  measures "d10062" horizontal distance of origin L0.start
  measures "d10063" vertical distance of origin L0.start
extrude "EXTRUDE - SOFFIT FILL UNDER" add sketch "OUTLINE - SOFFIT FILL UNDER" along normal blind 27 separate body makes body 23 in component "611203 AIR - SOFFIT FILL"
ref_plane "WorkPlane2" through (0, 0, 2134.1) normal (0, 0, 1) x (1, 0, 0) in component "611203 AIR - SOFFIT FILL"
sketch "OUTLINE - SOFFIT FILL UNDER OPENING 1" plane through (0, 0, 2134.1) normal (0, 0, 1) x (1, 0, 0) in component "611203 AIR - SOFFIT FILL"
  line L0 (493, -636.14) -> (505, -636.14)
  line L1 (505, -636.14) -> (505, -632.54)
  line L2 (505, -632.54) -> (493, -632.54)
  line L3 (493, -632.54) -> (493, -636.14)
  dimension "d10068" = 12
  dimension "d10070" = 493
  dimension "d10071" = 636.14
  constraint horizontal L0
  constraint vertical L1
  constraint horizontal L2
  constraint vertical L3
  measures "d10068" horizontal distance of L0.start L0.end
  measures "d10070" horizontal distance of origin L0.start
  measures "d10071" vertical distance of origin L0.start
extrude "CUT - SOFFIT FILL UNDER OPENING 1" cut sketch "OUTLINE - SOFFIT FILL UNDER OPENING 1" along normal blind 12 bodies 23 in component "611203 AIR - SOFFIT FILL"
ref_plane "WorkPlane3" through (0, 0, 2134.1) normal (0, 0, 1) x (1, 0, 0) in component "611203 AIR - SOFFIT FILL"
sketch "OUTLINE - SOFFIT FILL UNDER OPENING 2" plane through (0, 0, 2134.1) normal (0, 0, 1) x (1, 0, 0) in component "611203 AIR - SOFFIT FILL"
  line L0 (815.7, -636.14) -> (827.7, -636.14)
  line L1 (827.7, -636.14) -> (827.7, -632.54)
  line L2 (827.7, -632.54) -> (815.7, -632.54)
  line L3 (815.7, -632.54) -> (815.7, -636.14)
  dimension "d10076" = 12
  dimension "d10078" = 815.7
  dimension "d10079" = 636.14
  constraint horizontal L0
  constraint vertical L1
  constraint horizontal L2
  constraint vertical L3
  measures "d10076" horizontal distance of L0.start L0.end
  measures "d10078" horizontal distance of origin L0.start
  measures "d10079" vertical distance of origin L0.start
extrude "CUT - SOFFIT FILL UNDER OPENING 2" cut sketch "OUTLINE - SOFFIT FILL UNDER OPENING 2" along normal blind 12 bodies 23 in component "611203 AIR - SOFFIT FILL"
ref_plane "WorkPlane4" through (0, 0, 2134.1) normal (0, 0, 1) x (1, 0, 0) in component "611203 AIR - SOFFIT FILL"
sketch "OUTLINE - SOFFIT FILL UNDER OPENING 3" plane through (0, 0, 2134.1) normal (0, 0, 1) x (1, 0, 0) in component "611203 AIR - SOFFIT FILL"
  line L0 (1138.4, -636.14) -> (1150.4, -636.14)
  line L1 (1150.4, -636.14) -> (1150.4, -632.54)
  line L2 (1150.4, -632.54) -> (1138.4, -632.54)
  line L3 (1138.4, -632.54) -> (1138.4, -636.14)
  dimension "d10084" = 12
  dimension "d10086" = 1138.4
  dimension "d10087" = 636.14
  constraint horizontal L0
  constraint vertical L1
  constraint horizontal L2
  constraint vertical L3
  measures "d10084" horizontal distance of L0.start L0.end
  measures "d10086" horizontal distance of origin L0.start
  measures "d10087" vertical distance of origin L0.start
extrude "CUT - SOFFIT FILL UNDER OPENING 3" cut sketch "OUTLINE - SOFFIT FILL UNDER OPENING 3" along normal blind 12 bodies 23 in component "611203 AIR - SOFFIT FILL"
ref_plane "WorkPlane1" through (0, 0, 2159) normal (0, 0, 1) x (1, 0, 0) in component "611211 AIR - SOFFIT FILL - FRONT"
sketch "OUTLINE - SOFFIT FILL FRONT" plane through (0, 0, 2159) normal (0, 0, 1) x (1, 0, 0) in component "611211 AIR - SOFFIT FILL - FRONT"
  line L0 (-883, -322.14) -> (1161, -322.14)
  line L1 (1161, -322.14) -> (1161, -297)
  line L2 (1161, -297) -> (-883, -297)
  line L3 (-883, -297) -> (-883, -322.14)
  dimension "d10092" = 2044
  dimension "d10093" = 25.14
  dimension "d10094" = 883
  dimension "d10095" = 322.14
  constraint horizontal L0
  constraint vertical L1
  constraint horizontal L2
  constraint vertical L3
  measures "d10092" horizontal distance of L0.start L0.end
  measures "d10093" vertical distance of L0.start L2.end
  measures "d10094" horizontal distance of origin L0.start
  measures "d10095" vertical distance of origin L0.start
extrude "EXTRUDE - SOFFIT FILL FRONT" add sketch "OUTLINE - SOFFIT FILL FRONT" along normal blind 179.74 separate body makes body 24 in component "611211 AIR - SOFFIT FILL - FRONT"
ref_plane "WorkPlane1" through (0, 0, 2120) normal (0, 0, 1) x (1, 0, 0) in component "611204 AIR - EXHAUST GRILLE"
sketch "OUTLINE - EXHAUST GRILLE" plane through (0, 0, 2120) normal (0, 0, 1) x (1, 0, 0) in component "611204 AIR - EXHAUST GRILLE"
  line L0 (-1150, -633) -> (-885, -633)
  line L1 (-885, -633) -> (-885, -297)
  line L2 (-885, -297) -> (-1150, -297)
  line L3 (-1150, -297) -> (-1150, -633)
  dimension "d10100" = 265
  dimension "d10101" = 336
  dimension "d10102" = 1150
  dimension "d10103" = 633
  constraint horizontal L0
  constraint vertical L1
  constraint horizontal L2
  constraint vertical L3
  measures "d10100" horizontal distance of L0.start L0.end
  measures "d10101" vertical distance of L0.start L2.end
  measures "d10102" horizontal distance of origin L0.start
  measures "d10103" vertical distance of origin L0.start
extrude "EXTRUDE - EXHAUST GRILLE" add sketch "OUTLINE - EXHAUST GRILLE" along normal blind 2 separate body makes body 25 in component "611204 AIR - EXHAUST GRILLE"
sketch "OUTLINE - HANGER STUD" plane through (0, 0, 0) normal (0, 0, 1) x (1, 0, 0) in component "838001 HARDWARE - SOCKET HEAD BOLT - M6 X 16 - ISO 4762 8.8 ZINC"
  line L0 (0, 0) -> (10, 0)
  line L1 (10, 0) -> (10, 10)
  line L2 (10, 10) -> (0, 10)
  line L3 (0, 10) -> (0, 0)
  dimension "d10106" = 10
  dimension "d10107" = 10
  constraint horizontal L0
  constraint vertical L1
  constraint horizontal L2
  constraint vertical L3
  constraint vertical L0.start L3.end
  constraint horizontal L0.start L3.end
  measures "d10106" horizontal distance of L0.start L0.end
  measures "d10107" vertical distance of L0.start L2.end
extrude "EXTRUDE - HANGER STUD" add sketch "OUTLINE - HANGER STUD" along normal blind 6 separate body makes body 26 in component "838001 HARDWARE - SOCKET HEAD BOLT - M6 X 16 - ISO 4762 8.8 ZINC"
ref_plane "WorkPlane1" through (0, 0, 6) normal (0, 0, 1) x (1, 0, 0) in component "838001 HARDWARE - SOCKET HEAD BOLT - M6 X 16 - ISO 4762 8.8 ZINC"
sketch "OUTLINE - HANGER STUD SHANK" plane through (0, 0, 6) normal (0, 0, 1) x (1, 0, 0) in component "838001 HARDWARE - SOCKET HEAD BOLT - M6 X 16 - ISO 4762 8.8 ZINC"
  circle A0 centre (5, 5) radius 3
  dimension "d10112" = 6
  dimension "d10113" = 5
  dimension "d10114" = 5
  measures "d10112" diameter of A0
  measures "d10113" horizontal distance of origin A0.centre
  measures "d10114" vertical distance of origin A0.centre
extrude "EXTRUDE - HANGER STUD SHANK" add sketch "OUTLINE - HANGER STUD SHANK" along normal blind 7 bodies 26 in component "838001 HARDWARE - SOCKET HEAD BOLT - M6 X 16 - ISO 4762 8.8 ZINC"
ref_plane "WorkPlane1" through (0, 0, 2340.24) normal (0, 0, 1) x (1, 0, 0) in component "610201 AIR - SOFFIT"
sketch "PLACE - STUD L DOOR" plane through (0, 0, 2340.24) normal (0, 0, 1) x (1, 0, 0) in component "610201 AIR - SOFFIT"
  point P0 (-588, -640)
  dimension "d10119" = 588
  dimension "d10120" = 640
  measures "d10119" horizontal distance of origin P0
  measures "d10120" vertical distance of origin P0
ref_plane "WorkPlane2" through (0, 0, 2340.24) normal (0, 0, 1) x (1, 0, 0) in component "610201 AIR - SOFFIT"
sketch "PLACE - STUD L ROOM" plane through (0, 0, 2340.24) normal (0, 0, 1) x (1, 0, 0) in component "610201 AIR - SOFFIT"
  point P0 (-588, -296)
  dimension "d10127" = 588
  dimension "d10128" = 296
  measures "d10127" horizontal distance of origin P0
  measures "d10128" vertical distance of origin P0
ref_plane "WorkPlane3" through (0, 0, 2340.24) normal (0, 0, 1) x (1, 0, 0) in component "610201 AIR - SOFFIT"
sketch "PLACE - STUD R DOOR" plane through (0, 0, 2340.24) normal (0, 0, 1) x (1, 0, 0) in component "610201 AIR - SOFFIT"
  point P0 (578, -640)
  dimension "d10135" = 578
  dimension "d10136" = 640
  measures "d10135" horizontal distance of origin P0
  measures "d10136" vertical distance of origin P0
ref_plane "WorkPlane4" through (0, 0, 2340.24) normal (0, 0, 1) x (1, 0, 0) in component "610201 AIR - SOFFIT"